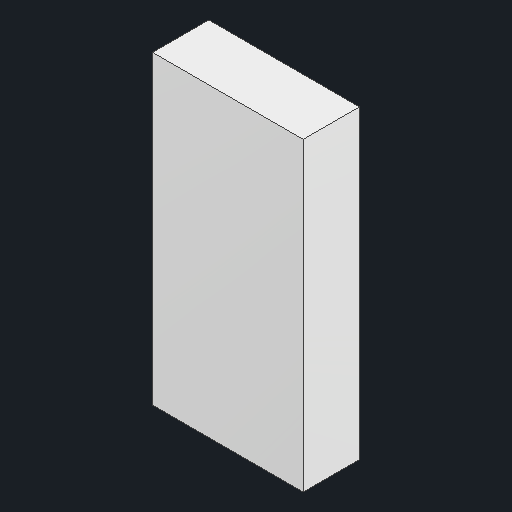
# Autodesk Inventor part: Part3
Saved by Autodesk Inventor 2027.1 (Build 311270010, 270A)
## iProperties
Created: 2024-04-23
Part Number: Part3
Material: ABS Plastic
Document SubType Name: Modeling
Designer: - LENOVO -
Density: 1.06 g/cm^3
Appearance: Smooth - White
Author: - LENOVO -
Autodesk Inventor part; units mm, degrees
ref_plane "YZ Plane" through (0, 0, 0) normal (1, 0, 0) x (0, 1, 0)
ref_plane "XZ Plane" through (0, 0, 0) normal (0, 1, 0) x (-1, 0, 0)
ref_plane "XY Plane" through (0, 0, 0) normal (0, 0, 1) x (1, 0, 0)
sketch "Sketch1" plane through (0, 0, 0) normal (0, 0, 1) x (1, 0, 0)
  line L0 (5.1426, -1.7252) -> (3.5355, -1.7252)
  line L1 (3.5355, -1.7252) -> (3.5355, -4.9841)
  line L2 (3.5355, -4.9841) -> (5.1426, -4.9841)
  line L3 (5.1426, -4.9841) -> (5.1426, -1.7252)
  point P0 (0, 0)
  constraints: 8 end point, 2 parallel, 1 horizontal, 1 perpendicular
extrude "Extrusion1" add sketch "Sketch1" along normal blind 0.6
body "Solid1"
